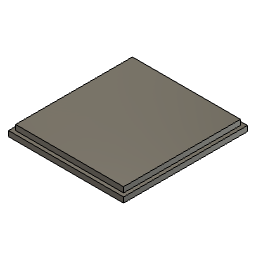
tapa_pata (Autodesk Fusion 360 design; units mm, degrees)
Autodesk Fusion 360 part; units mm, degrees
sketch "Sketch1" plane through (0, 0, 0) normal (0, 1, 0) x (1, 0, 0)
  line L0 (32.5, 35) -> (-32.5, 35)
  line L1 (-32.5, 35) -> (-32.5, -35)
  line L2 (-32.5, -35) -> (32.5, -35)
  line L3 (32.5, -35) -> (32.5, 35)
  line L4 (32.5, 35) -> (-32.5, -35) construction
  line L5 (-32.5, 35) -> (32.5, -35) construction
  dimension "d1" = 65
  dimension "d2" = 70
  constraint horizontal L0
  constraint perpendicular L0 L1
  constraint parallel L0 L2
  constraint parallel L1 L3
  constraint coincident L4 origin
  constraint coincident L5 origin
  measures "d1" distance of L1.end L2.end
  measures "d2" distance of L0.end L1.end
extrude "Extrude1" add sketch "Sketch1" along normal blind 3
sketch "Sketch2" plane through (0, 3, 0) normal (0, 1, 0) x (-1, 0, 0)
  line L0 (-32.5, 35) -> (-32.5, -35)
  line L1 (-32.5, -35) -> (32.5, -35)
  line L2 (32.5, -35) -> (32.5, 35)
  line L3 (32.5, 35) -> (-32.5, 35)
  line L4 (30.5, 33) -> (-30.5, 33)
  line L5 (-30.5, 33) -> (-30.5, -33)
  line L6 (-30.5, -33) -> (30.5, -33)
  line L7 (30.5, -33) -> (30.5, 33)
  line L8 (30.5, 33) -> (-30.5, -33) construction
  line L9 (-30.5, 33) -> (30.5, -33) construction
  dimension "d5" = 61
  dimension "d6" = 66
  constraint horizontal L4
  constraint perpendicular L4 L5
  constraint parallel L4 L6
  constraint parallel L5 L7
  constraint coincident L8 origin
  constraint coincident L9 origin
  measures "d5" distance of L5.end L6.end
  measures "d6" distance of L4.end L5.end
extrude "Extrude2" add sketch "Sketch2" along normal blind 3 contours L4 L5 L6 L7
